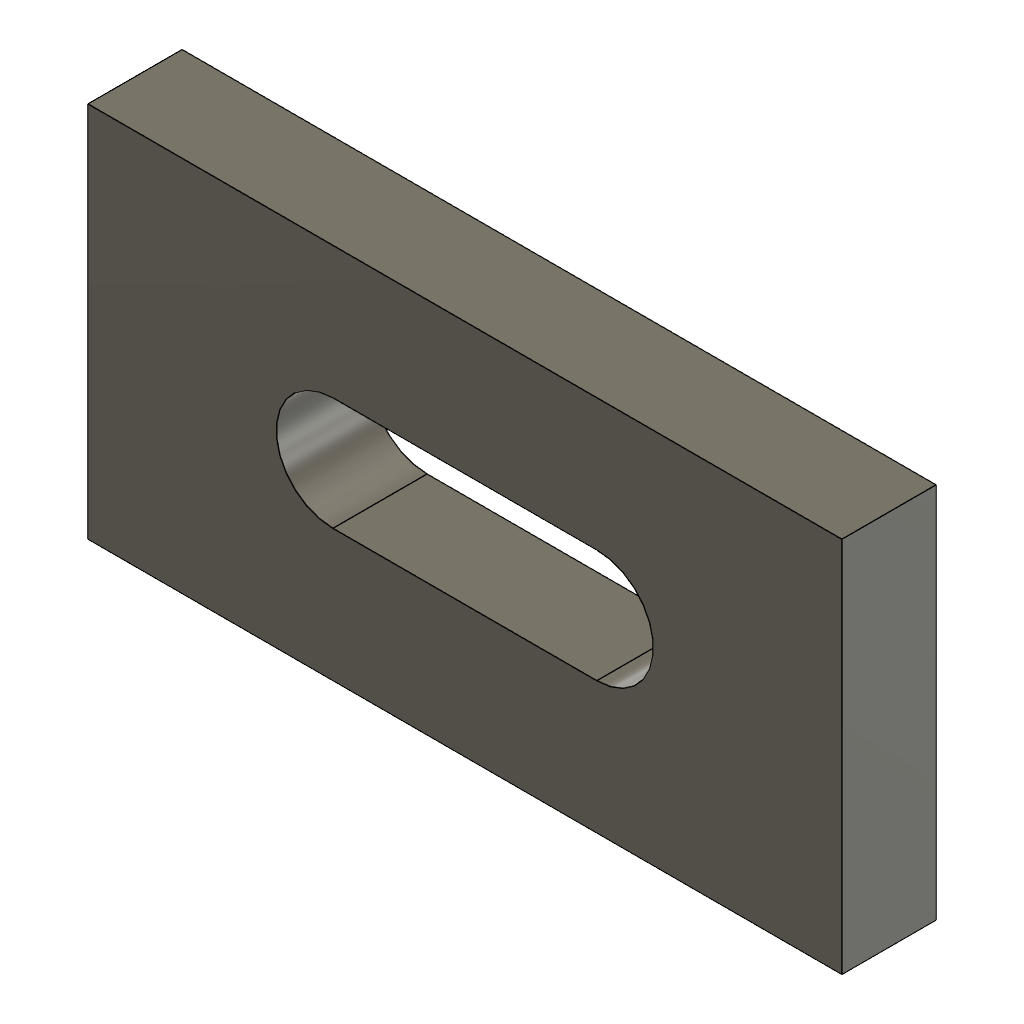
sk_slot_overall_cut (Autodesk Fusion 360 design; units mm, degrees)
part number: 2026-11-13-14-34-54-696
Autodesk Fusion 360 part; units mm, degrees
sketch "Sketch1" plane through (0, 0, 0) normal (0, 0, 1) x (1, 0, 0)
  line L0 (-10, -10) -> (30, -10)
  line L1 (30, -10) -> (30, 10)
  line L2 (30, 10) -> (-10, 10)
  line L3 (-10, 10) -> (-10, -10)
extrude "Extrude1" add sketch "Sketch1" along normal blind 5
sketch "Sketch2" plane through (0, 0, 0) normal (0, 0, 1) x (1, 0, 0)
  line L0 (3, -3) -> (17, -3)
  arc A0 (17, -3) -> (17, 3) centre (17, 0) ccw
  line L1 (17, 3) -> (3, 3)
  arc A1 (3, 3) -> (3, -3) centre (3, 0) ccw
  line L2 (0, 0) -> (20, 0) construction
  constraint coincident A1 L2.start
  constraint coincident A0 L2.end
  constraint coincident A1.centre L2
  constraint coincident A0.centre L2
  constraint tangent L0 A0
  constraint tangent A0 L1
  constraint tangent L1 A1
  constraint tangent L0 A1
  constraint parallel L0 L1
extrude "Extrude2" cut sketch "Sketch2" along normal through all
